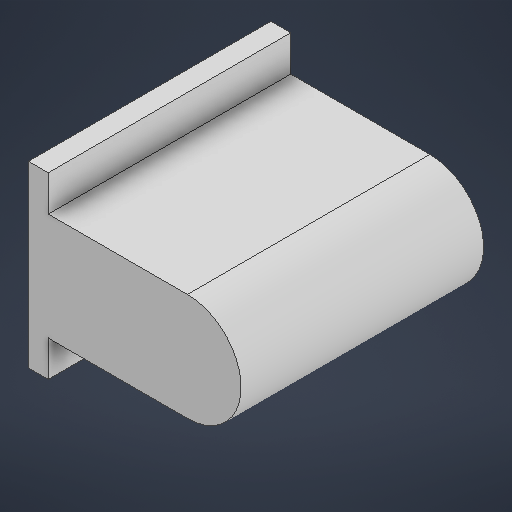
# Autodesk Inventor part: 6_11_piece_mobile_detection4
Saved by Autodesk Inventor 2026 (Build 300175000, 175)
## iProperties
Created: 2025-06-25
Part Number: 6_11_piece_mobile_detection4
Material: Générique
Document SubType Name: Modeling
Designer: virgi
Density: 1 g/cm^3
Appearance: Par défaut
Author: virgi
Autodesk Inventor part; units mm, degrees
ref_plane "YZ Plane" through (0, 0, 0) normal (1, 0, 0) x (0, 1, 0)
ref_plane "XZ Plane" through (0, 0, 0) normal (0, 1, 0) x (-1, 0, 0)
ref_plane "XY Plane" through (0, 0, 0) normal (0, 0, 1) x (1, 0, 0)
sketch "Esquisse1" plane through (0, 0, 0) normal (0, 0, 1) x (1, 0, 0)
  line L0 (0, 2.25) -> (0.5, 2.25)
  line L1 (0.5, -2.25) -> (0, -2.25)
  line L2 (0, -2.25) -> (0, 2.25)
  line L3 (0.5, 1.35) -> (4, 1.35)
  line L4 (4, -1.35) -> (0.5, -1.35)
  line L5 (0, 0) -> (13.403, 0) construction
  line L6 (0.5, 2.25) -> (0.5, 1.35)
  line L7 (0.5, -1.35) -> (0.5, -2.25)
  arc A0 (4, -1.35) -> (4, 1.35) centre (4, 0) ccw
  line L8 (4, 1.35) -> (4, -1.35) construction
  dimension "d0" = 4.5
  dimension "d3" = 0.5
  dimension "d4" = 2.7
  dimension "d7" = 3.5
  constraints: 18 end point, 4 parallel, 3 equal length, 3 horizontal, 3 perpendicular, 2 midpoint, 2 point on circle, 1 centre point, 1 coincident, 1 point on line
  measures "d0" distance of L1.end L0.start
  measures "d3" distance between parallel lines of L6 L2
  measures "d4" distance between parallel lines of L4 L3
  measures "d7" distance from line of L6 L3.end
extrude "Extrusion1" add sketch "Esquisse1" along normal blind 6.1
